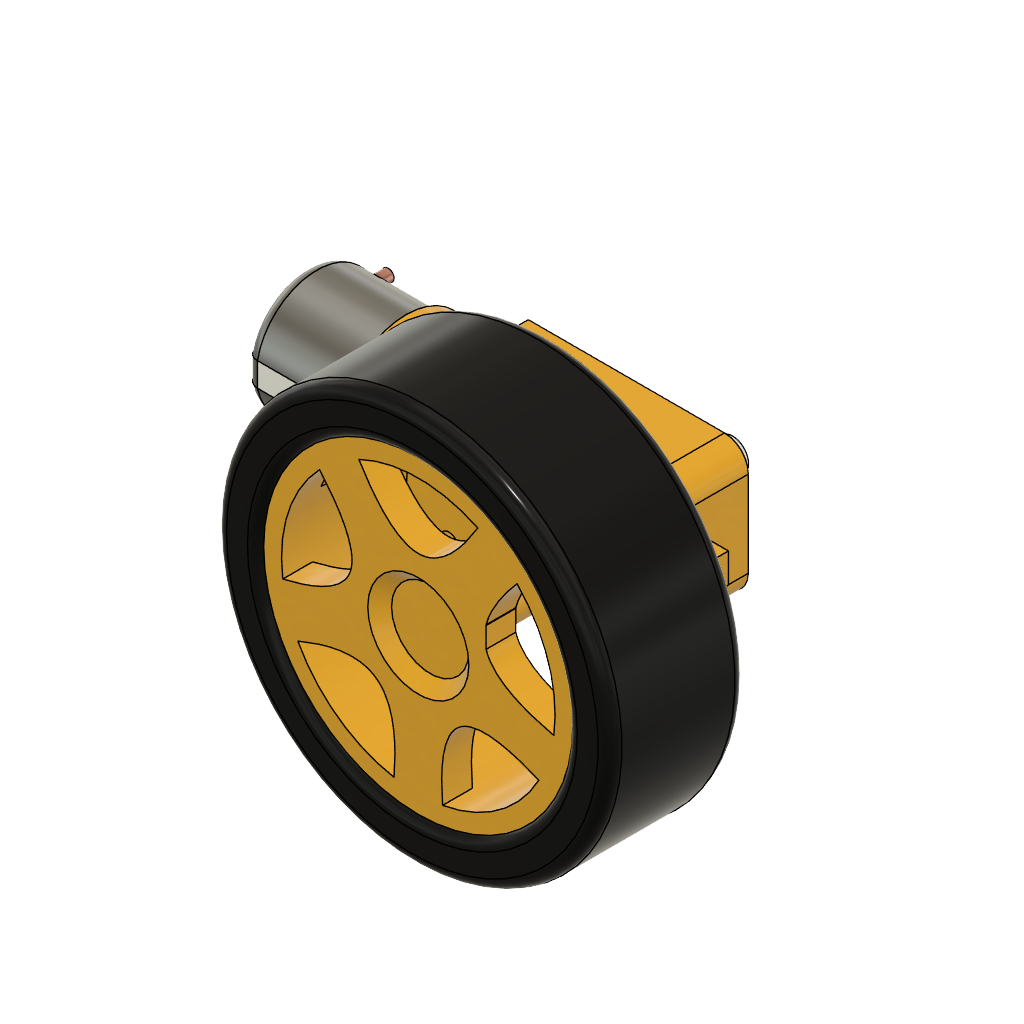
yellow-motor-wheel (Autodesk Fusion 360 design; units mm, degrees)
Autodesk Fusion 360 part; units mm, degrees
sketch "Sketch1" plane through (0, 0, 0) normal (0, 0, 1) x (1, 0, 0)
  circle A0 centre (0, 0) radius 2.7
  line L0 (0, 0) -> (-11.25, 0) construction
  circle A1 centre (-11.25, 0) radius 2
  line L1 (-53.6, 11.22) -> (7.4, 11.22)
  line L2 (11.4, 7.22) -> (11.4, -7.22)
  line L3 (7.4, -11.22) -> (-53.6, -11.22)
  line L4 (-53.6, -11.22) -> (-53.6, 11.22)
  circle A2 centre (-19.85, 8.8) radius 1.5
  circle A3 centre (-19.85, -8.8) radius 1.5
  line L5 (-19.85, -8.8) -> (-19.85, 8.8) construction
  line L6 (-19.85, 0) -> (-11.25, 0) construction
  arc A4 (11.4, 7.22) -> (7.4, 11.22) centre (7.4, 7.22) ccw
  arc A5 (7.4, -11.22) -> (11.4, -7.22) centre (7.4, -7.22) ccw
  line L7 (11.4, 2.5) -> (16.2, 2.5)
  line L8 (16.2, 2.5) -> (16.2, -2.5)
  line L9 (16.2, -2.5) -> (11.4, -2.5)
  circle A6 centre (14, 0) radius 1.5
  line L10 (0, 0) -> (21.6739, 0) construction
  line L11 (-53.6, 6.5) -> (-30.6, 6.5)
  line L12 (-30.6, 6.5) -> (-30.6, -6.5)
  line L13 (-30.6, -6.5) -> (-53.6, -6.5)
  line L14 (-30.6, 2.5) -> (-34.6, 2.5)
  line L15 (-34.6, 2.5) -> (-34.6, -2.5)
  line L16 (-34.6, -2.5) -> (-30.6, -2.5)
  circle A7 centre (-48.6, 6.5) radius 1
  circle A8 centre (-48.6, -6.5) radius 1
  line L17 (-48.6, 6.5) -> (-48.6, -6.5) construction
  point P0 (11.4, 11.22)
  point P1 (11.4, -11.22)
  dimension "d1" = 5.4
  dimension "d2" = 4
  dimension "d4" = 65
  dimension "d5" = 11.25
  dimension "d7" = 22.44
  dimension "d8" = 11.22
  dimension "d9" = 3
  dimension "d10" = 3
  dimension "d11" = 8.6
  dimension "d12" = 17.6
  dimension "d13" = 4
  dimension "d14" = 5
  dimension "d15" = 2.5
  dimension "d16" = 4.8
  dimension "d17" = 3
  dimension "d18" = 2.6
  dimension "d34" = 13
  dimension "d35" = 6.5
  dimension "d36" = 23
  dimension "d37" = 5
  dimension "d38" = 2.5
  dimension "d39" = 4
  dimension "d46" = 2
  dimension "d47" = 2
  dimension "d48" = 13
  dimension "d49" = 6.5
  dimension "d50" = 5
  dimension "d53" = 14
  constraint coincident A0.centre L0.start
  constraint horizontal L0
  constraint coincident L0.end A1.centre
  constraint horizontal L1
  constraint vertical L2
  constraint horizontal L3
  constraint vertical L4
  constraint coincident A3.centre L5.start
  constraint coincident A2.centre L5.end
  constraint perpendicular L3 L5
  constraint midpoint L5 L6.start
  constraint horizontal L6
  constraint coincident P0 L1
  constraint coincident P0 L2
  constraint tangent L1 A4
  constraint tangent L2 A4
  constraint coincident P1 L2
  constraint coincident P1 L3
  constraint tangent L2 A5
  constraint tangent L3 A5
  constraint equal A4 A5
  constraint coincident L2 L7.start
  constraint perpendicular L2 L7
  constraint perpendicular L7 L8
  constraint coincident L2 L9.end
  constraint perpendicular L2 L9
  constraint parallel L0 L10
  constraint coincident A6.centre L10
  constraint coincident L4 L11.start
  constraint perpendicular L4 L11
  constraint perpendicular L11 L12
  constraint coincident L4 L13.end
  constraint perpendicular L4 L13
  constraint coincident L12 L14.start
  constraint perpendicular L12 L14
  constraint perpendicular L14 L15
  constraint coincident L12 L16.end
  constraint perpendicular L15 L16
  constraint coincident A7.centre L17.start
  constraint coincident A8.centre L17.end
  constraint vertical L17
  measures "d1" diameter of A0
  measures "d2" diameter of A1
  measures "d4" distance of L1.start P0
  measures "d5" distance of A0.centre L0.end
  measures "d7" distance of P0 P1
  measures "d8" distance of A0.centre L3
  measures "d9" diameter of A2
  measures "d10" diameter of A3
  measures "d11" distance of L0.end L5
  measures "d12" distance of A3.centre A2.centre
  measures "d13" radius of A4
  measures "d14" distance of L7 L9
  measures "d15" distance of L0 L9
  measures "d16" distance of L7.start L7.end
  measures "d17" diameter of A6
  measures "d18" distance of L2 A6.centre
  measures "d34" distance of L11 L13
  measures "d35" distance of L6 L13
  measures "d36" distance of L12.end L13.end
  measures "d37" distance of L14 L16
  measures "d38" distance of L6 L16
  measures "d39" distance of L12 L15
  measures "d46" diameter of A7
  measures "d47" diameter of A8
  measures "d48" distance of A7.centre A8.centre
  measures "d49" distance of L6 A7.centre
  measures "d50" distance of L4 L17
  measures "d53" distance of A0.centre A6.centre
extrude "Extrude1" add sketch "Sketch1" along normal mid plane 19.1 contours A0 | A1 | L1 L2 L3 L4 A4 A5 L11 L12 L13 A7 A8 | L4 L11 L12 L13 L14 L15 L16 A7 A8 | L11 A7 | L11 A7 | L13 A8 | L13 A8 | L12 L14 L15 L16 makes body 1
extrude "Extrude2" add sketch "Sketch1" along normal mid plane 2.8 separate body contours L2 L7 L8 L9 makes body 2
extrude "Extrude3" add sketch "Sketch1" along normal blind 2 from surface at 9.55 contours A1 bodies 1 2
extrude "Extrude4" add sketch "Sketch1" along normal blind 18.3 contours A0 bodies 2 1
extrude "Extrude15" add sketch "Sketch1" against normal blind 18.3 separate body contours A0 makes body 3
extrude "Extrude7" add sketch "Sketch1" along normal mid plane 20 contours L4 L11 L12 L13 L14 L15 L16 A7 A8 | L11 A7 | L13 A8 | L12 L14 L15 L16 picked at (-48.5751, 5.9711) picked at (-48.5751, -5.8783) bodies 2 1
sketch "Sketch2" plane through (-53.6, 0, 0) normal (-1, 0, 0) x (0, 0, 1)
  line L0 (-9.55, -11.22) -> (9.55, -11.22)
  line L1 (9.55, 6.5) -> (9.55, 11.22)
  line L2 (9.55, 11.22) -> (-9.55, 11.22)
  line L3 (-9.55, 11.22) -> (-9.55, 6.5)
  circle A0 centre (0, 0) radius 11.22
  circle A1 centre (0, 0) radius 10.2
  line L4 (-12.0156, 13.5571) -> (14.4289, 13.5571)
  line L5 (14.4289, 13.5571) -> (14.4289, -14.6967)
  line L6 (14.4289, -14.6967) -> (-12.0156, -14.6967)
  line L7 (-12.0156, -14.6967) -> (-12.0156, 13.5571)
  line L8 (-9.55, 6.5) -> (-10, 6.5)
  line L9 (-10, 6.5) -> (-10, -6.5)
  line L10 (-10, -6.5) -> (-9.55, -6.5)
  line L11 (-9.55, -6.5) -> (-9.55, -11.22)
  line L12 (9.55, -11.22) -> (9.55, -6.5)
  line L13 (9.55, -6.5) -> (10, -6.5)
  line L14 (10, -6.5) -> (10, 6.5)
  line L15 (10, 6.5) -> (9.55, 6.5)
  dimension "d28" = 22.44
  dimension "d29" = 20.4
  constraint coincident A0.centre A1.centre
  constraint concentric A0 A1
  constraint horizontal L4
  constraint vertical L5
  constraint horizontal L6
  constraint vertical L7
  measures "d28" diameter of A0
  measures "d29" diameter of A1
extrude "Extrude5" cut sketch "Sketch2" against normal blind 28 contours L0 A0 L9 L10 L11 | L0 A0 L12 L13 L14 | L2 L3 A0 L8 L9 | L1 L2 A0 L14 L15 | L4 L5 L6 L7 bodies 1 2
extrude "Extrude6" cut sketch "Sketch2" against normal blind 17 contours A0 A1 L9 L14 | A0 A1 L9 | A0 A1 L14 | A0 A1 L9 L14 bodies 2 1
extrude "Extrude8" add sketch "Sketch1" along normal mid plane 22.4 contours L12 L14 L15 L16 bodies 2 1
fillet "Fillet1" radius 2 1 faces at (-53.6, -4.5206, -1.2015) on bodies 1
extrude "Extrude9" add sketch "Sketch1" against normal blind 9 contours L11 A7 | L11 A7 | L13 A8 | L13 A8 bodies 1 2
sketch "Sketch3" plane through (0, 0, 9.55) normal (0, 0, 1) x (1, 0, 0)
  circle A0 centre (0, 0) radius 2.7
  circle A1 centre (-11.25, 0) radius 2
  circle A2 centre (-19.85, -8.8) radius 1.5
  circle A3 centre (-19.85, 8.8) radius 1.5
  line L0 (-25.6, 11.22) -> (-25.6, 5.8895)
  line L1 (-25.6, 5.8895) -> (-30.6, 5.8895)
  line L2 (-30.6, 5.8895) -> (-30.6, -5.8895)
  line L3 (-30.6, -5.8895) -> (-25.6, -5.8895)
  line L4 (-25.6, -5.8895) -> (-25.6, -11.22)
  line L5 (-25.6, -11.22) -> (7.4, -11.22)
  arc A4 (7.4, -11.22) -> (11.4, -7.22) centre (7.4, -7.22) ccw
  line L6 (11.4, -7.22) -> (11.4, 7.22)
  arc A5 (11.4, 7.22) -> (7.4, 11.22) centre (7.4, 7.22) ccw
  line L7 (7.4, 11.22) -> (-25.6, 11.22)
  circle A6 centre (0, 0) radius 4.65
  circle A7 centre (0, 0) radius 33.25
  circle A8 centre (0, 0) radius 26
  circle A9 centre (0, 0) radius 23
  spline S0 degree 5 poles (-10, 20.7123) (-9.6, 20.0515) (-8.8, 18.7876) (-7.6, 17.0649) (-6, 15.1198) (-4, 13.315) (-2, 12.1926) (0, 11.8084) (2, 12.1926) (4, 13.315) (6, 15.1198) (7.6, 17.0649) (8.8, 18.7876) (9.6, 20.0515) (10, 20.7123) knots 0 0 0 0 0 0 0.1 0.2 0.3 0.4 0.5 0.6 0.7 0.8 0.9 1 1 1 1 1 1
  line L8 (0, 0) -> (0, 46) construction
  spline S1 degree 5 poles (-22.7888, -3.1101) (-22.0367, -2.9339) (-20.5874, -2.5636) (-18.5782, -1.9547) (-16.2339, -1.0341) (-13.8994, 0.3103) (-12.2139, 1.8656) (-11.2304, 3.649) (-10.9779, 5.6698) (-11.4273, 7.9188) (-12.5257, 10.3786) (-13.8811, 12.5014) (-15.1487, 14.175) (-16.1036, 15.3264) (-16.6084, 15.911) knots 0 0 0 0 0 0 0.1 0.2 0.3 0.4 0.5 0.6 0.7 0.8 0.9 1 1 1 1 1 1
  spline S2 degree 5 poles (-4.0842, -22.6345) (-4.0194, -21.8647) (-3.9237, -20.372) (-3.8819, -18.2729) (-4.0331, -15.7589) (-4.5903, -13.1232) (-5.5486, -11.0396) (-6.9408, -9.5532) (-8.7847, -8.6885) (-11.0624, -8.4209) (-13.7413, -8.7055) (-16.179, -9.3386) (-18.1624, -10.027) (-19.5525, -10.5793) (-20.2646, -10.8788) knots 0 0 0 0 0 0 0.1 0.2 0.3 0.4 0.5 0.6 0.7 0.8 0.9 1 1 1 1 1 1
  spline S3 degree 5 poles (20.2646, -10.8788) (19.5525, -10.5793) (18.1624, -10.027) (16.179, -9.3386) (13.7413, -8.7055) (11.0624, -8.4209) (8.7847, -8.6885) (6.9408, -9.5532) (5.5486, -11.0396) (4.5903, -13.1232) (4.0331, -15.7589) (3.8819, -18.2729) (3.9237, -20.372) (4.0194, -21.8647) (4.0842, -22.6345) knots 0 0 0 0 0 0 0.1 0.2 0.3 0.4 0.5 0.6 0.7 0.8 0.9 1 1 1 1 1 1
  spline S4 degree 5 poles (16.6084, 15.911) (16.1036, 15.3264) (15.1487, 14.175) (13.8811, 12.5014) (12.5257, 10.3786) (11.4273, 7.9188) (10.9779, 5.6698) (11.2304, 3.649) (12.2139, 1.8656) (13.8994, 0.3103) (16.2339, -1.0341) (18.5782, -1.9547) (20.5874, -2.5636) (22.0367, -2.9339) (22.7888, -3.1101) knots 0 0 0 0 0 0 0.1 0.2 0.3 0.4 0.5 0.6 0.7 0.8 0.9 1 1 1 1 1 1
  circle A10 centre (0, 0) radius 8.5
  point P0 (0, 12)
  point P1 (-11.4127, 3.7082)
  point P2 (-7.0534, -9.7082)
  point P3 (7.0534, -9.7082)
  point P4 (11.4127, 3.7082)
  dimension "d54" = 9.3
  dimension "d55" = 66.5
  dimension "d56" = 52
  dimension "d62" = 3
  dimension "d73" = 20
  dimension "d74" = 10
  dimension "d75" = 11
  dimension "d77" = 360
  dimension "d78" = 17
  constraint concentric A0 A6
  constraint concentric A6 A7
  constraint concentric A7 A8
  constraint concentric A8 A9
  constraint coincident A9 S0.start
  constraint coincident A9 S0.end
  constraint coincident A0.centre A6.centre
  constraint vertical L8
  constraint concentric A9 A10
  measures "d54" diameter of A6
  measures "d55" diameter of A7
  measures "d56" diameter of A8
  measures "d62" distance of A8 A9
  measures "d73" distance of S0.start S0.end
  measures "d74" distance of S0.start L8
  measures "d75" distance of A9 P0
  measures "d78" diameter of A10
extrude "Extrude10" add sketch "Sketch3" along normal blind 20 separate body contours A6 makes body 4
extrude "Extrude11" add sketch "Sketch3" along normal blind 5 from surface at 20 contours A0 | A1 | A2 A9 | A2 L5 A4 L6 A5 L7 A9 S1 S2 S3 S4 | A2 A9 | A2 A3 L5 L7 A8 A9 | A3 A9 | A5 L7 A9 S0 S1 S4 | L5 L7 A8 A9 | L5 A9 S2 S3 | L6 A5 S4 | A4 L6 A9 S3 S4 | A6 | A10 picked at (-21.0904, 9.3499) bodies 4
extrude "Extrude12" add sketch "Sketch3" against normal blind 16 from surface at 20 contours A2 A3 L5 L7 A8 A9 | L5 L7 A8 A9 bodies 4
extrude "Extrude13" add sketch "Sketch3" along normal blind 1 and the other way blind 22 from surface at 25 contours L0 L1 L2 L3 L4 L5 L7 A8 | A7 bodies 4
fillet "Fillet2" radius 2 2 faces at (30.6127, -2.9436, 35.55) (30.7095, -1.6519, 12.55) on bodies 4
extrude "Extrude14" cut sketch "Sketch3" against normal blind 2 from surface at 25 contours A0 | A6 | A10 bodies 4
chamfer "Chamfer1" distance 2 angle 45 1 edges at (-7.9248, 3.0737, 32.55) tangent chain off on bodies 4
equation "d8 = d7 / 2"
equation "d10 = d9"
equation "d15 = d14 / 2"
equation "d19 = ( 19.1 ) * 1 mm"
equation "d26 = 36.6 mm / 2"
equation "d35 = d34 / 2"
equation "d38 = d37 / 2"
equation "d47 = d46"
equation "d49 = d48 / 2"
equation "d74 = d73 / 2"
equation "d83 = ( -36.6 / 2 ) * 1 mm"
named bodies: "Motor", "Wheel", "Axel2", "Extension"
